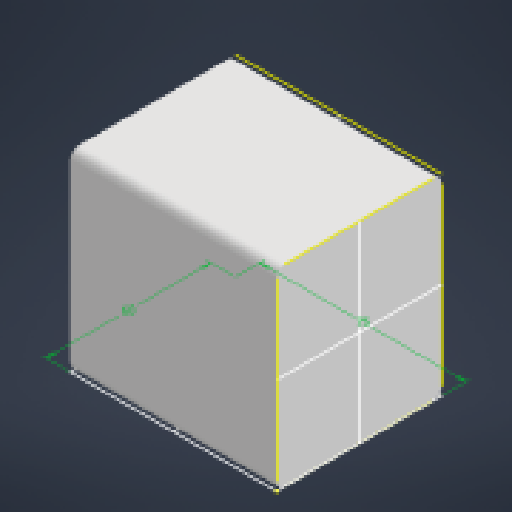
# Autodesk Inventor part: Pin 7.8Ah
Saved by Autodesk Inventor 2027 (Build 310192060, 192F)
## iProperties
Created: 2026-07-08
Part Number: Pin 7.8Ah
Material: Generic
Document SubType Name: Modeling
Designer: Laptop
Density: 1 g/cm^3
Appearance: Default
Author: Laptop
Autodesk Inventor part; units mm, degrees
ref_plane "YZ Plane" through (0, 0, 0) normal (1, 0, 0) x (0, 1, 0)
ref_plane "XZ Plane" through (0, 0, 0) normal (0, 1, 0) x (-1, 0, 0)
ref_plane "XY Plane" through (0, 0, 0) normal (0, 0, 1) x (1, 0, 0)
sketch "Sketch1" plane through (0, 0, 0) normal (0, 1, 0) x (-1, 0, 0)
  line L0 (0, 0) -> (75, 0)
  line L1 (75, 0) -> (75, -60)
  line L2 (75, -60) -> (0, -60)
  line L3 (0, -60) -> (0, 0)
  line L4 (37.5, 0) -> (37.5, -60)
  line L5 (75, -30) -> (0, -30)
  dimension "d0" = 75
  dimension "d1" = 60
  constraints: 12 end point, 4 midpoint, 2 parallel, 1 horizontal, 1 perpendicular
  measures "d0" distance of L1.end L2.end
  measures "d1" distance of L0.end L1.end
extrude "Extrusion1" add sketch "Sketch1" along normal blind 70
fillet "Fillet1" radius 3 1 edges at (-37.5, 70, 0)
fillet "Fillet2" radius 3 3 edges at (-37.5, 70, -60) (-37.5, 0, 0) (-37.5, 0, -60)
sketch "Sketch2" plane through (0, 0, -3) normal (1, 0, 0) x (0, 0, -1)
  line L0 (0, 0) -> (54, 0) projected
  line L1 (27, 0) -> (27, 70)
  line L2 (0, 70) -> (54, 70) projected
  line L3 (-3, 3) -> (-3, 67) projected
  line L4 (-3, 35) -> (57, 35)
  line L5 (57, 3) -> (57, 67) projected
  point P0 (-3, 0)
  constraints: 4 end point, 4 midpoint
sketch "Sketch3" plane through (0, 3, -60) normal (0, 0, -1) x (-1, 0, 0)
  line L0 (75, -3) -> (0, -3) projected
  line L1 (37.5, -3) -> (37.5, 67)
  line L2 (0, 67) -> (75, 67) projected
  line L3 (75, 0) -> (75, 64) projected
  line L4 (75, 0) -> (75, 64) projected
  line L5 (75, 32) -> (0, 32)
  line L6 (0, 0) -> (0, 64) projected
  constraints: 4 end point, 4 midpoint
sketch "Sketch4" plane through (-75, 67, 0) normal (0, 0, 1) x (1, 0, 0)
  line L0 (75, 3) -> (0, 3) projected
  line L1 (37.5, 3) -> (37.5, -67)
  line L2 (75, -64) -> (0, -64) projected
  line L3 (75, -64) -> (75, 0) projected
  line L4 (75, -32) -> (0, -32)
  line L5 (0, -64) -> (0, 0) projected
  point P0 (75, -67)
  constraints: 4 end point, 3 midpoint, 1 perpendicular
sketch "Sketch5" plane through (-75, 0, -57) normal (-1, 0, 0) x (0, 0, 1)
  line L0 (54, 70) -> (0, 70) projected
  line L1 (27, 70) -> (27, 0)
  line L2 (54, 0) -> (0, 0) projected
  line L3 (57, 3) -> (57, 67) projected
  line L4 (57, 35) -> (-3, 35)
  line L5 (-3, 3) -> (-3, 67) projected
  line L6 (57, 70) -> (57, 0) projected
  dimension "d6" = 70
  constraints: 4 end point, 4 midpoint
  measures "d6" distance of point (57, 0) L6.start
sketch "Sketch6" plane through (0, 70, 0) normal (0, 1, 0) x (1, 0, 0)
  line L0 (0, 60) -> (-75, 60) projected
  line L1 (-37.5, 60) -> (-37.5, 0)
  line L2 (-75, 0) -> (0, 0) projected
  line L3 (0, 3) -> (0, 57) projected
  line L4 (0, 30) -> (-75, 30)
  line L5 (-75, 57) -> (-75, 3) projected
  constraints: 4 end point, 4 midpoint
body "Solid1"
